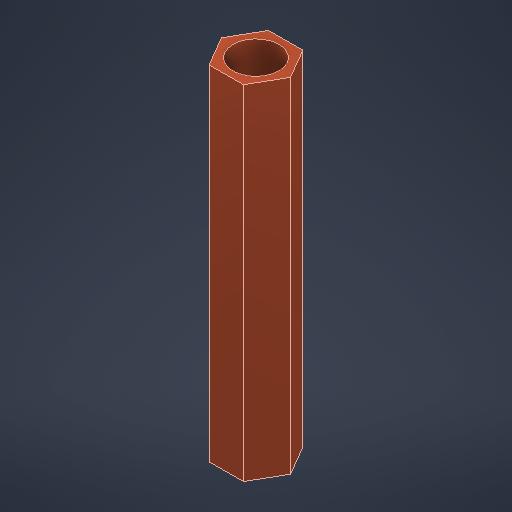
# Autodesk Inventor part: Remache
Saved by Autodesk Inventor 2026.1 (Build 301233020, 233B)
## iProperties
Created: 2026-08-15
Part Number: Remache
Material: Genérico
Document SubType Name: Modeling
Designer: allan
Density: 1 g/cm^3
Appearance: Cobre - Satinado
Author: allan
Autodesk Inventor part; units mm, degrees
ref_plane "YZ Plane" through (0, 0, 0) normal (1, 0, 0) x (0, 1, 0)
ref_plane "XZ Plane" through (0, 0, 0) normal (0, 1, 0) x (-1, 0, 0)
ref_plane "XY Plane" through (0, 0, 0) normal (0, 0, 1) x (1, 0, 0)
sketch "Boceto1" plane through (0, 0, 0) normal (0, 1, 0) x (-1, 0, 0)
  line L0 (-1.5, 0) -> (-0.75, 1.299)
  line L1 (-0.75, 1.299) -> (0.75, 1.299)
  line L2 (0.75, 1.299) -> (1.5, 0)
  line L3 (1.5, 0) -> (0.75, -1.299)
  line L4 (0.75, -1.299) -> (-0.75, -1.299)
  line L5 (-0.75, -1.299) -> (-1.5, 0)
  circle A0 centre (0, 0) radius 3
  line L6 (0, 3) -> (2.5981, 1.5)
  line L7 (2.5981, 1.5) -> (2.5981, -1.5)
  line L8 (2.5981, -1.5) -> (0, -3)
  line L9 (0, -3) -> (-2.5981, -1.5)
  line L10 (-2.5981, -1.5) -> (-2.5981, 1.5)
  line L11 (-2.5981, 1.5) -> (0, 3)
  circle A1 centre (0, 0) radius 1
  dimension "d6" = 6
  dimension "d10" = 2
  constraints: 24 end point, 3 coincident, 1 centre point, 1 vertical alignment, 28 other
  measures "d10" diameter of A1
extrude "Extrusión1" add sketch "Boceto1" along normal blind 30 contours L0 L1 L2 L3 L4 L5 | A1
sketch "Boceto2" plane through (0, 30, 0) normal (0, 1, 0) x (1, 0, 0)
  circle A0 centre (0, 0) radius 1
  dimension "d3" = 2
  constraints: 1 centre point, 1 coincident
  measures "d3" diameter of A0
extrude "Extrusión2" cut sketch "Boceto2" against normal blind 30
sketch "Boceto3" plane through (0, 30, 0) normal (0, 1, 0) x (1, 0, 0)
  circle A0 centre (0, 0) radius 3
  line L0 (-1.4914, -2.603) -> (-3, -0.01)
  line L1 (-3, -0.01) -> (-1.5086, 2.5931)
  line L2 (-1.5086, 2.5931) -> (1.4914, 2.603)
  line L3 (1.4914, 2.603) -> (3, 0.01)
  line L4 (3, 0.01) -> (1.5086, -2.5931)
  line L5 (1.5086, -2.5931) -> (-1.4914, -2.603)
  dimension "d7" = 6
  constraints: 12 end point, 2 coincident, 16 other
extrude "Extrusión3" add sketch "Boceto3" against normal blind 30 contours L4 L5 L0 L1 L2 L3
sketch "Boceto6" plane through (0, 30, 0) normal (0, 1, 0) x (1, 0, 0)
  circle A0 centre (0, 0) radius 2
  dimension "d14" = 4
  constraints: 1 centre point, 1 coincident
  measures "d14" diameter of A0
extrude "Extrusión5" cut sketch "Boceto6" against normal blind 35.75
